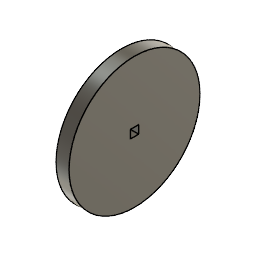
Wheel (Autodesk Fusion 360 design; units mm, degrees)
Autodesk Fusion 360 part; units mm, degrees
sketch "Sketch1" plane through (0, 0, 0) normal (1, 0, 0) x (0, 1, 0)
  circle A0 centre (0, 0) radius 25.4
  line L0 (1.6002, 1.6002) -> (-1.6002, 1.6002)
  line L1 (-1.6002, 1.6002) -> (-1.6002, -1.6002)
  line L2 (-1.6002, -1.6002) -> (1.6002, -1.6002)
  line L3 (1.6002, -1.6002) -> (1.6002, 1.6002)
  line L4 (1.6002, 1.6002) -> (-1.6002, -1.6002) construction
  line L5 (-1.6002, 1.6002) -> (1.6002, -1.6002) construction
  dimension "d1" = 50.8
  dimension "d2" = 3.2004
  dimension "d3" = 3.2004
  constraint coincident A0.centre origin
  constraint horizontal L0
  constraint perpendicular L0 L1
  constraint parallel L0 L2
  constraint parallel L1 L3
  constraint coincident L4 A0.centre
  constraint coincident L5 A0.centre
  measures "d1" diameter of A0
  measures "d2" distance of L0.end L1.end
  measures "d3" distance of L1.end L2.end
extrude "Extrude1" add sketch "Sketch1" along normal blind 5.08
